Autodesk Fusion 360 part; units mm, degrees
(part 3 of 3)
  line L550 (6.0052, -30.2752) -> (6.2606, -30.3962)
  line L551 (6.2606, -30.3962) -> (6.5639, -30.8872)
  line L552 (6.5639, -30.8872) -> (7.2119, -30.7424)
  line L553 (7.2119, -30.7424) -> (7.2773, -30.1689)
  line L554 (7.2773, -30.1689) -> (7.4569, -29.9507)
  line L555 (7.4569, -29.9507) -> (7.6639, -29.8488)
  line L556 (7.6639, -29.8488) -> (7.8943, -29.8384)
  line L557 (7.8943, -29.8384) -> (8.1569, -29.9431)
  line L558 (8.1569, -29.9431) -> (8.4904, -30.4141)
  line L559 (8.4904, -30.4141) -> (9.128, -30.2289)
  line L560 (9.128, -30.2289) -> (9.1573, -29.6525)
  line L561 (9.1573, -29.6525) -> (9.3228, -29.4234)
  line L562 (9.3228, -29.4234) -> (9.523, -29.3087)
  line L563 (9.523, -29.3087) -> (9.7523, -29.2839)
  line L564 (9.7523, -29.2839) -> (10.0209, -29.3719)
  line L565 (10.0209, -29.3719) -> (10.3833, -29.821)
  line L566 (10.3833, -29.821) -> (11.0081, -29.5961)
  line L567 (11.0081, -29.5961) -> (11.0011, -29.019)
  line L568 (11.0011, -29.019) -> (11.1519, -28.78)
  line L569 (11.1519, -28.78) -> (11.3445, -28.6529)
  line L570 (11.3445, -28.6529) -> (11.5718, -28.6137)
  line L571 (11.5718, -28.6137) -> (11.8454, -28.6847)
  line L572 (11.8454, -28.6847) -> (12.2353, -29.1102)
  line L573 (12.2353, -29.1102) -> (12.8447, -28.8465)
  line L574 (12.8447, -28.8465) -> (12.8015, -28.2709)
  line L575 (12.8015, -28.2709) -> (12.9371, -28.0229)
  line L576 (12.9371, -28.0229) -> (13.1212, -27.884)
  line L577 (13.1212, -27.884) -> (13.3457, -27.8307)
  line L578 (13.3457, -27.8307) -> (13.6232, -27.8843)
  line L579 (13.6232, -27.8843) -> (14.039, -28.2845)
  line L580 (14.039, -28.2845) -> (14.6307, -27.983)
  line L581 (14.6307, -27.983) -> (14.5514, -27.4113)
  line L582 (14.5514, -27.4113) -> (14.6711, -27.1553)
  line L583 (14.6711, -27.1553) -> (14.8462, -27.0051)
  line L584 (14.8462, -27.0051) -> (15.0668, -26.9378)
  line L585 (15.0668, -26.9378) -> (15.3471, -26.9739)
  line L586 (15.3471, -26.9739) -> (15.7873, -27.3471)
  line L587 (15.7873, -27.3471) -> (16.3589, -27.0091)
  line L588 (16.3589, -27.0091) -> (16.2438, -26.4436)
  line L589 (16.2438, -26.4436) -> (16.3472, -26.1805)
  line L590 (16.3472, -26.1805) -> (16.5126, -26.0196)
  line L591 (16.5126, -26.0196) -> (16.7285, -25.9385)
  line L592 (16.7285, -25.9385) -> (17.0106, -25.957)
  line L593 (17.0106, -25.957) -> (17.4733, -26.3019)
  line L594 (17.4733, -26.3019) -> (18.0225, -25.9287)
  line L595 (18.0225, -25.9287) -> (17.8722, -25.3714)
  line L596 (17.8722, -25.3714) -> (17.9589, -25.1024)
  line L597 (17.9589, -25.1024) -> (18.1138, -24.9315)
  line L598 (18.1138, -24.9315) -> (18.3242, -24.837)
  line L599 (18.3242, -24.837) -> (18.6068, -24.8377)
  line L600 (18.6068, -24.8377) -> (19.0903, -25.1528)
  line L601 (19.0903, -25.1528) -> (19.615, -24.7458)
  line L602 (19.615, -24.7458) -> (19.43, -24.1992)
  line L603 (19.43, -24.1992) -> (19.4996, -23.9252)
  line L604 (19.4996, -23.9252) -> (19.6435, -23.7449)
  line L605 (19.6435, -23.7449) -> (19.8476, -23.6374)
  line L606 (19.8476, -23.6374) -> (20.1297, -23.6203)
  line L607 (20.1297, -23.6203) -> (20.632, -23.9045)
  line L608 (20.632, -23.9045) -> (21.1301, -23.4654)
  line L609 (21.1301, -23.4654) -> (20.9111, -22.9314)
  line L610 (20.9111, -22.9314) -> (20.9634, -22.6536)
  line L611 (20.9634, -22.6536) -> (21.0957, -22.4646)
  line L612 (21.0957, -22.4646) -> (21.2926, -22.3445)
  line L613 (21.2926, -22.3445) -> (21.5731, -22.3098)
  line L614 (21.5731, -22.3098) -> (22.0923, -22.5618)
  line L615 (22.0923, -22.5618) -> (22.5618, -22.0923)
  line L616 (22.5618, -22.0923) -> (22.3098, -21.5731)
  line L617 (22.3098, -21.5731) -> (22.3445, -21.2926)
  line L618 (22.3445, -21.2926) -> (22.4646, -21.0957)
  line L619 (22.4646, -21.0957) -> (22.6536, -20.9634)
  line L620 (22.6536, -20.9634) -> (22.9314, -20.9111)
  line L621 (22.9314, -20.9111) -> (23.4654, -21.1301)
  line L622 (23.4654, -21.1301) -> (23.9045, -20.632)
  line L623 (23.9045, -20.632) -> (23.6203, -20.1297)
  line L624 (23.6203, -20.1297) -> (23.6374, -19.8476)
  line L625 (23.6374, -19.8476) -> (23.7449, -19.6435)
  line L626 (23.7449, -19.6435) -> (23.9252, -19.4996)
  line L627 (23.9252, -19.4996) -> (24.1992, -19.43)
  line L628 (24.1992, -19.43) -> (24.7458, -19.615)
  line L629 (24.7458, -19.615) -> (25.1528, -19.0903)
  line L630 (25.1528, -19.0903) -> (24.8377, -18.6068)
  line L631 (24.8377, -18.6068) -> (24.837, -18.3242)
  line L632 (24.837, -18.3242) -> (24.9315, -18.1138)
  line L633 (24.9315, -18.1138) -> (25.1024, -17.9589)
  line L634 (25.1024, -17.9589) -> (25.3714, -17.8722)
  line L635 (25.3714, -17.8722) -> (25.9287, -18.0225)
  line L636 (25.9287, -18.0225) -> (26.3019, -17.4733)
  line L637 (26.3019, -17.4733) -> (25.957, -17.0106)
  line L638 (25.957, -17.0106) -> (25.9385, -16.7285)
  line L639 (25.9385, -16.7285) -> (26.0196, -16.5126)
  line L640 (26.0196, -16.5126) -> (26.1805, -16.3472)
  line L641 (26.1805, -16.3472) -> (26.4436, -16.2438)
  line L642 (26.4436, -16.2438) -> (27.0091, -16.3589)
  line L643 (27.0091, -16.3589) -> (27.3471, -15.7873)
  line L644 (27.3471, -15.7873) -> (26.9739, -15.3471)
  line L645 (26.9739, -15.3471) -> (26.9378, -15.0668)
  line L646 (26.9378, -15.0668) -> (27.0051, -14.8462)
  line L647 (27.0051, -14.8462) -> (27.1553, -14.6711)
  line L648 (27.1553, -14.6711) -> (27.4113, -14.5514)
  line L649 (27.4113, -14.5514) -> (27.983, -14.6307)
  line L650 (27.983, -14.6307) -> (28.2845, -14.039)
  line L651 (28.2845, -14.039) -> (27.8843, -13.6232)
  line L652 (27.8843, -13.6232) -> (27.8307, -13.3457)
  line L653 (27.8307, -13.3457) -> (27.884, -13.1212)
  line L654 (27.884, -13.1212) -> (28.0229, -12.9371)
  line L655 (28.0229, -12.9371) -> (28.2709, -12.8015)
  line L656 (28.2709, -12.8015) -> (28.8465, -12.8447)
  line L657 (28.8465, -12.8447) -> (29.1102, -12.2353)
  line L658 (29.1102, -12.2353) -> (28.6847, -11.8454)
  line L659 (28.6847, -11.8454) -> (28.6137, -11.5718)
  line L660 (28.6137, -11.5718) -> (28.6529, -11.3445)
  line L661 (28.6529, -11.3445) -> (28.78, -11.1519)
  line L662 (28.78, -11.1519) -> (29.019, -11.0011)
  line L663 (29.019, -11.0011) -> (29.5961, -11.0081)
  line L664 (29.5961, -11.0081) -> (29.821, -10.3833)
  line L665 (29.821, -10.3833) -> (29.3719, -10.0209)
  line L666 (29.3719, -10.0209) -> (29.2839, -9.7523)
  line L667 (29.2839, -9.7523) -> (29.3087, -9.523)
  line L668 (29.3087, -9.523) -> (29.4234, -9.3228)
  line L669 (29.4234, -9.3228) -> (29.6525, -9.1573)
  line L670 (29.6525, -9.1573) -> (30.2289, -9.128)
  line L671 (30.2289, -9.128) -> (30.4141, -8.4904)
  line L672 (30.4141, -8.4904) -> (29.9431, -8.1569)
  line L673 (29.9431, -8.1569) -> (29.8384, -7.8943)
  line L674 (29.8384, -7.8943) -> (29.8488, -7.6639)
  line L675 (29.8488, -7.6639) -> (29.9507, -7.4569)
  line L676 (29.9507, -7.4569) -> (30.1689, -7.2773)
  line L677 (30.1689, -7.2773) -> (30.7424, -7.2119)
  line L678 (30.7424, -7.2119) -> (30.8872, -6.5639)
  line L679 (30.8872, -6.5639) -> (30.3962, -6.2606)
  line L680 (30.3962, -6.2606) -> (30.2752, -6.0052)
  line L681 (30.2752, -6.0052) -> (30.2711, -5.7745)
  line L682 (30.2711, -5.7745) -> (30.3599, -5.5616)
  line L683 (30.3599, -5.5616) -> (30.5664, -5.3686)
  line L684 (30.5664, -5.3686) -> (31.1346, -5.2674)
  line L685 (31.1346, -5.2674) -> (31.2384, -4.6115)
  line L686 (31.2384, -4.6115) -> (30.7293, -4.3397)
  line L687 (30.7293, -4.3397) -> (30.5926, -4.0923)
  line L688 (30.5926, -4.0923) -> (30.574, -3.8624)
  line L689 (30.574, -3.8624) -> (30.6492, -3.6443)
  line L690 (30.6492, -3.6443) -> (30.8431, -3.4387)
  line L691 (30.8431, -3.4387) -> (31.4039, -3.302)
  line L692 (31.4039, -3.302) -> (31.4664, -2.641)
  line L693 (31.4664, -2.641) -> (30.9412, -2.4016)
  line L694 (30.9412, -2.4016) -> (30.7892, -2.1633)
  line L695 (30.7892, -2.1633) -> (30.7562, -1.935)
  line L696 (30.7562, -1.935) -> (30.8175, -1.7126)
  line L697 (30.8175, -1.7126) -> (30.9982, -1.4953)
  line L698 (30.9982, -1.4953) -> (31.5492, -1.3237)
  line L699 (31.5492, -1.3237) -> (31.5701, -0.66)
extrude "Extrude1'''''''''''" add sketch "Sketch1 (12)" along normal blind 11 separate body makes body 12 in component "print_pulley_100T"
ref_plane "WorkPlane2" through (0, 0, 7.5) normal (0, 0, 1) x (1, 0, 0) in component "print_pulley_100T"
sketch "Sketch2 (12)" plane through (0, 0, 7.5) normal (0, 0, 1) x (1, 0, 0) in component "print_pulley_100T"
  line L0 (14.607, 0) -> (7.3035, 12.65)
  line L1 (7.3035, 12.65) -> (-7.3035, 12.65)
  line L2 (-7.3035, 12.65) -> (-14.607, 0)
  line L3 (-14.607, 0) -> (-7.3035, -12.65)
  line L4 (-7.3035, -12.65) -> (7.3035, -12.65)
  line L5 (7.3035, -12.65) -> (14.607, 0)
extrude "Extrude2'''''''''''" cut sketch "Sketch2 (12)" along normal blind 11 bodies 12 in component "print_pulley_100T"
ref_plane "WorkPlane1" through (0, 0, 17.9) normal (0, 0, 1) x (1, 0, 0) in component "print_idler_spacer_top"
sketch "Sketch1 (13)" plane through (0, 0, 17.9) normal (0, 0, 1) x (1, 0, 0) in component "print_idler_spacer_top"
  circle A0 centre (-12.2, -48.6) radius 4
extrude "Extrude1''''''''''''" add sketch "Sketch1 (13)" along normal blind 10.1 separate body makes body 13 in component "print_idler_spacer_top"
ref_plane "WorkPlane2" through (0, 0, 17.5) normal (0, 0, 1) x (1, 0, 0) in component "print_idler_spacer_top"
sketch "Sketch2 (13)" plane through (0, 0, 17.5) normal (0, 0, 1) x (1, 0, 0) in component "print_idler_spacer_top"
  circle A0 centre (-12.2, -48.6) radius 2.4
extrude "Extrude2''''''''''''" add sketch "Sketch2 (13)" along normal blind 0.4 bodies 13 in component "print_idler_spacer_top"
ref_plane "WorkPlane3" through (0, 0, 17.5) normal (0, 0, 1) x (1, 0, 0) in component "print_idler_spacer_top"
sketch "Sketch3 (9)" plane through (0, 0, 17.5) normal (0, 0, 1) x (1, 0, 0) in component "print_idler_spacer_top"
  circle A0 centre (-12.2, -48.6) radius 1.7
extrude "Extrude3''''''''" cut sketch "Sketch3 (9)" along normal blind 10.5 bodies 13 in component "print_idler_spacer_top"
ref_plane "WorkPlane1" through (0, 0, 6) normal (0, 0, 1) x (1, 0, 0) in component "print_idler_spacer_low"
sketch "Sketch1 (14)" plane through (0, 0, 6) normal (0, 0, 1) x (1, 0, 0) in component "print_idler_spacer_low"
  circle A0 centre (-12.2, -48.6) radius 4.25
extrude "Extrude1'''''''''''''" add sketch "Sketch1 (14)" along normal blind 2.6 separate body makes body 14 in component "print_idler_spacer_low"
ref_plane "WorkPlane2" through (0, 0, 8.6) normal (0, 0, 1) x (1, 0, 0) in component "print_idler_spacer_low"
sketch "Sketch2 (14)" plane through (0, 0, 8.6) normal (0, 0, 1) x (1, 0, 0) in component "print_idler_spacer_low"
  circle A0 centre (-12.2, -48.6) radius 2.4
extrude "Extrude2'''''''''''''" add sketch "Sketch2 (14)" along normal blind 0.4 bodies 14 in component "print_idler_spacer_low"
ref_plane "WorkPlane3" through (0, 0, 6) normal (0, 0, 1) x (1, 0, 0) in component "print_idler_spacer_low"
sketch "Sketch3 (10)" plane through (0, 0, 6) normal (0, 0, 1) x (1, 0, 0) in component "print_idler_spacer_low"
  circle A0 centre (-12.2, -48.6) radius 1.7
extrude "Extrude3'''''''''" cut sketch "Sketch3 (10)" along normal blind 3 bodies 14 in component "print_idler_spacer_low"
ref_plane "WorkPlane4" through (0, 0, 6) normal (0, 0, 1) x (1, 0, 0) in component "print_idler_spacer_low"
sketch "Sketch4 (8)" plane through (0, 0, 6) normal (0, 0, 1) x (1, 0, 0) in component "print_idler_spacer_low"
  line L0 (-8.9091, -48.6) -> (-10.5546, -45.75)
  line L1 (-10.5546, -45.75) -> (-13.8454, -45.75)
  line L2 (-13.8454, -45.75) -> (-15.4909, -48.6)
  line L3 (-15.4909, -48.6) -> (-13.8454, -51.45)
  line L4 (-13.8454, -51.45) -> (-10.5546, -51.45)
  line L5 (-10.5546, -51.45) -> (-8.9091, -48.6)
extrude "Extrude4'''''''" cut sketch "Sketch4 (8)" along normal blind 1.9 bodies 14 in component "print_idler_spacer_low"
ref_plane "WorkPlane1" through (0, 0, 9) normal (0, 0, 1) x (1, 0, 0) in component "koop_idler_2xF623"
sketch "Sketch1 (15)" plane through (0, 0, 9) normal (0, 0, 1) x (1, 0, 0) in component "koop_idler_2xF623"
  circle A0 centre (-12.2, -48.6) radius 5
extrude "Extrude1''''''''''''''" add sketch "Sketch1 (15)" along normal blind 8.5 separate body makes body 15 in component "koop_idler_2xF623"
ref_plane "WorkPlane2" through (0, 0, 9) normal (0, 0, 1) x (1, 0, 0) in component "koop_idler_2xF623"
sketch "Sketch2 (15)" plane through (0, 0, 9) normal (0, 0, 1) x (1, 0, 0) in component "koop_idler_2xF623"
  circle A0 centre (-12.2, -48.6) radius 1.5
extrude "Extrude2''''''''''''''" cut sketch "Sketch2 (15)" along normal blind 8.5 bodies 15 in component "koop_idler_2xF623"
ref_plane "WorkPlane1" through (0, 0, 0) normal (0, 0, 1) x (1, 0, 0) in component "print_fit_seat"
sketch "Sketch1 (16)" plane through (0, 0, 0) normal (0, 0, 1) x (1, 0, 0) in component "print_fit_seat"
  circle A0 centre (150, 0) radius 24
extrude "Extrude1'''''''''''''''" add sketch "Sketch1 (16)" along normal blind 9 separate body makes body 16 in component "print_fit_seat"
ref_plane "WorkPlane2" through (0, 0, 0) normal (0, 0, 1) x (1, 0, 0) in component "print_fit_seat"
sketch "Sketch2 (16)" plane through (0, 0, 0) normal (0, 0, 1) x (1, 0, 0) in component "print_fit_seat"
  circle A0 centre (150, 0) radius 19.5
extrude "Extrude2'''''''''''''''" cut sketch "Sketch2 (16)" along normal blind 9 bodies 16 in component "print_fit_seat"
ref_plane "WorkPlane3" through (0, 0, 0) normal (0, 0, 1) x (1, 0, 0) in component "print_fit_seat"
sketch "Sketch3 (11)" plane through (0, 0, 0) normal (0, 0, 1) x (1, 0, 0) in component "print_fit_seat"
  circle A0 centre (150, 0) radius 21.075
extrude "Extrude3''''''''''" cut sketch "Sketch3 (11)" along normal blind 7.3 bodies 16 in component "print_fit_seat"
ref_plane "WorkPlane4" through (0, 0, 0) normal (0, 0, 1) x (1, 0, 0) in component "print_fit_seat"
sketch "Sketch4 (9)" plane through (0, 0, 0) normal (0, 0, 1) x (1, 0, 0) in component "print_fit_seat"
  circle A0 centre (150, 0) radius 21.375
extrude "Extrude4''''''''" cut sketch "Sketch4 (9)" along normal blind 0.3 bodies 16 in component "print_fit_seat"
ref_plane "WorkPlane1" through (0, 0, 0) normal (0, 0, 1) x (1, 0, 0) in component "print_fit_shaft"
sketch "Sketch1 (17)" plane through (0, 0, 0) normal (0, 0, 1) x (1, 0, 0) in component "print_fit_shaft"
  circle A0 centre (150, 60) radius 14.95
extrude "Extrude1''''''''''''''''" add sketch "Sketch1 (17)" along normal blind 8 separate body makes body 17 in component "print_fit_shaft"
ref_plane "WorkPlane2" through (0, 0, 8) normal (0, 0, 1) x (1, 0, 0) in component "print_fit_shaft"
sketch "Sketch2 (17)" plane through (0, 0, 8) normal (0, 0, 1) x (1, 0, 0) in component "print_fit_shaft"
  line L0 (164.4338, 60) -> (157.2169, 72.5)
  line L1 (157.2169, 72.5) -> (142.7831, 72.5)
  line L2 (142.7831, 72.5) -> (135.5662, 60)
  line L3 (135.5662, 60) -> (142.7831, 47.5)
  line L4 (142.7831, 47.5) -> (157.2169, 47.5)
  line L5 (157.2169, 47.5) -> (164.4338, 60)
extrude "Extrude2''''''''''''''''" add sketch "Sketch2 (17)" along normal blind 8 bodies 17 in component "print_fit_shaft"
ref_plane "WorkPlane1" through (0, 0, -35) normal (0, 0, 1) x (1, 0, 0) in component "koop_motor_17HE15"
sketch "Sketch1 (18)" plane through (0, 0, -35) normal (0, 0, 1) x (1, 0, 0) in component "koop_motor_17HE15"
  line L0 (-21, -76.7) -> (21, -76.7)
  line L1 (21, -76.7) -> (21, -34.7)
  line L2 (21, -34.7) -> (-21, -34.7)
  line L3 (-21, -34.7) -> (-21, -76.7)
extrude "Extrude1'''''''''''''''''" add sketch "Sketch1 (18)" along normal blind 38 separate body makes body 18 in component "koop_motor_17HE15"
ref_plane "WorkPlane2" through (0, 0, 3) normal (0, 0, 1) x (1, 0, 0) in component "koop_motor_17HE15"
sketch "Sketch2 (18)" plane through (0, 0, 3) normal (0, 0, 1) x (1, 0, 0) in component "koop_motor_17HE15"
  circle A0 centre (0, -55.7) radius 11
extrude "Extrude2'''''''''''''''''" add sketch "Sketch2 (18)" along normal blind 2 bodies 18 in component "koop_motor_17HE15"
ref_plane "WorkPlane3" through (0, 0, 5) normal (0, 0, 1) x (1, 0, 0) in component "koop_motor_17HE15"
sketch "Sketch3 (12)" plane through (0, 0, 5) normal (0, 0, 1) x (1, 0, 0) in component "koop_motor_17HE15"
  circle A0 centre (0, -55.7) radius 2.5
extrude "Extrude3'''''''''''" add sketch "Sketch3 (12)" along normal blind 21.5 bodies 18 in component "koop_motor_17HE15"
ref_plane "WorkPlane1" through (0, 0, 8.5) normal (0, 0, 1) x (1, 0, 0) in component "koop_pulley_16T_5mm"
sketch "Sketch1 (19)" plane through (0, 0, 8.5) normal (0, 0, 1) x (1, 0, 0) in component "koop_pulley_16T_5mm"
  circle A0 centre (0, -55.7) radius 6
extrude "Extrude1''''''''''''''''''" add sketch "Sketch1 (19)" along normal blind 16 separate body makes body 19 in component "koop_pulley_16T_5mm"
ref_plane "WorkPlane2" through (0, 0, 8.5) normal (0, 0, 1) x (1, 0, 0) in component "koop_pulley_16T_5mm"
sketch "Sketch2 (19)" plane through (0, 0, 8.5) normal (0, 0, 1) x (1, 0, 0) in component "koop_pulley_16T_5mm"
  circle A0 centre (0, -55.7) radius 2.5
extrude "Extrude2''''''''''''''''''" cut sketch "Sketch2 (19)" along normal blind 16 bodies 19 in component "koop_pulley_16T_5mm"
ref_plane "WorkPlane1" through (0, 0, 34) normal (0, 0, 1) x (1, 0, 0) in component "koop_6806_lower"
sketch "Sketch1 (20)" plane through (0, 0, 34) normal (0, 0, 1) x (1, 0, 0) in component "koop_6806_lower"
  circle A0 centre (0, 0) radius 21
extrude "Extrude1'''''''''''''''''''" add sketch "Sketch1 (20)" along normal blind 7 separate body makes body 20 in component "koop_6806_lower"
ref_plane "WorkPlane2" through (0, 0, 34) normal (0, 0, 1) x (1, 0, 0) in component "koop_6806_lower"
sketch "Sketch2 (20)" plane through (0, 0, 34) normal (0, 0, 1) x (1, 0, 0) in component "koop_6806_lower"
  circle A0 centre (0, 0) radius 15
extrude "Extrude2'''''''''''''''''''" cut sketch "Sketch2 (20)" along normal blind 7 bodies 20 in component "koop_6806_lower"
ref_plane "WorkPlane1" through (0, 0, 74) normal (0, 0, 1) x (1, 0, 0) in component "koop_6806_upper"
sketch "Sketch1 (21)" plane through (0, 0, 74) normal (0, 0, 1) x (1, 0, 0) in component "koop_6806_upper"
  circle A0 centre (0, 0) radius 21
extrude "Extrude1''''''''''''''''''''" add sketch "Sketch1 (21)" along normal blind 7 separate body makes body 21 in component "koop_6806_upper"
ref_plane "WorkPlane2" through (0, 0, 74) normal (0, 0, 1) x (1, 0, 0) in component "koop_6806_upper"
sketch "Sketch2 (21)" plane through (0, 0, 74) normal (0, 0, 1) x (1, 0, 0) in component "koop_6806_upper"
  circle A0 centre (0, 0) radius 15
extrude "Extrude2''''''''''''''''''''" cut sketch "Sketch2 (21)" along normal blind 7 bodies 21 in component "koop_6806_upper"
ref_plane "WorkPlane1" through (0, 0, 3.5) normal (0, 0, 1) x (1, 0, 0) in component "koop_magnet_D6x2.5"
sketch "Sketch1 (22)" plane through (0, 0, 3.5) normal (0, 0, 1) x (1, 0, 0) in component "koop_magnet_D6x2.5"
  circle A0 centre (0, 0) radius 3
extrude "Extrude1'''''''''''''''''''''" add sketch "Sketch1 (22)" along normal blind 2.5 separate body makes body 22 in component "koop_magnet_D6x2.5"
component "print_bottom_plate" placed x (1, 0, 0) y (0, 1, 0) z (0, 0, 1) at (0, 0, 0)
component "print_top_plate" placed x (1, 0, 0) y (0, 1, 0) z (0, 0, 1) at (0, 0, 0)
component "print_pillar" placed x (1, 0, 0) y (0, 1, 0) z (0, 0, 1) at (0, 0, 0)
component "print_pillar" placed x (1, 0, 0) y (0, 1, 0) z (0, 0, 1) at (112, 0, 0)
component "print_pillar" placed x (1, 0, 0) y (0, 1, 0) z (0, 0, 1) at (112, -112, 0)
component "print_pillar" placed x (1, 0, 0) y (0, 1, 0) z (0, 0, 1) at (0, -112, 0)
component "print_foot" placed x (1, 0, 0) y (0, 1, 0) z (0, 0, 1) at (0, 0, 0)
component "print_foot" placed x (1, 0, 0) y (0, 1, 0) z (0, 0, 1) at (120, 0, 0)
component "print_foot" placed x (1, 0, 0) y (0, 1, 0) z (0, 0, 1) at (100, 140, 0)
component "print_foot" placed x (1, 0, 0) y (0, 1, 0) z (0, 0, 1) at (20, 140, 0)
component "print_bearing_housing" placed x (1, 0, 0) y (0, 1, 0) z (0, 0, 1) at (0, 0, 0)
component "print_output_shaft" placed x (1, 0, 0) y (0, 1, 0) z (0, 0, 1) at (0, 0, 0)
component "print_magnet_holder" placed x (1, 0, 0) y (0, 1, 0) z (0, 0, 1) at (0, 0, 0)
component "print_camera_plate" placed x (1, 0, 0) y (0, 1, 0) z (0, 0, 1) at (0, 0, 0)
component "print_sensor_tray" placed x (1, 0, 0) y (0, 1, 0) z (0, 0, 1) at (0, 0, 0)
component "print_spacer" placed x (1, 0, 0) y (0, 1, 0) z (0, 0, 1) at (0, 0, 0)
component "print_pulley_120T" placed x (1, 0, 0) y (0, 1, 0) z (0, 0, 1) at (0, 0, 0)
component "print_pulley_100T" placed x (1, 0, 0) y (0, 1, 0) z (0, 0, 1) at (0, 0, 0)
component "print_idler_spacer_top" placed x (1, 0, 0) y (0, 1, 0) z (0, 0, 1) at (0, 0, 0)
component "print_idler_spacer_low" placed x (1, 0, 0) y (0, 1, 0) z (0, 0, 1) at (0, 0, 0)
component "koop_idler_2xF623" placed x (1, 0, 0) y (0, 1, 0) z (0, 0, 1) at (0, 0, 0)
component "print_idler_spacer_top" placed x (1, 0, 0) y (0, 1, 0) z (0, 0, 1) at (24.4, 0, 0)
component "print_idler_spacer_low" placed x (1, 0, 0) y (0, 1, 0) z (0, 0, 1) at (24.4, 0, 0)
component "koop_idler_2xF623" placed x (1, 0, 0) y (0, 1, 0) z (0, 0, 1) at (24.4, 0, 0)
component "print_fit_seat" placed x (1, 0, 0) y (0, 1, 0) z (0, 0, 1) at (0, 0, 0)
component "print_fit_shaft" placed x (1, 0, 0) y (0, 1, 0) z (0, 0, 1) at (0, 0, 0)
component "koop_motor_17HE15" placed x (1, 0, 0) y (0, 1, 0) z (0, 0, 1) at (0, 0, 0)
component "koop_pulley_16T_5mm" placed x (1, 0, 0) y (0, 1, 0) z (0, 0, 1) at (0, 0, 0)
component "koop_6806_lower" placed x (1, 0, 0) y (0, 1, 0) z (0, 0, 1) at (0, 0, 0)
component "koop_6806_upper" placed x (1, 0, 0) y (0, 1, 0) z (0, 0, 1) at (0, 0, 0)
component "koop_magnet_D6x2.5" placed x (1, 0, 0) y (0, 1, 0) z (0, 0, 1) at (0, 0, 0)
